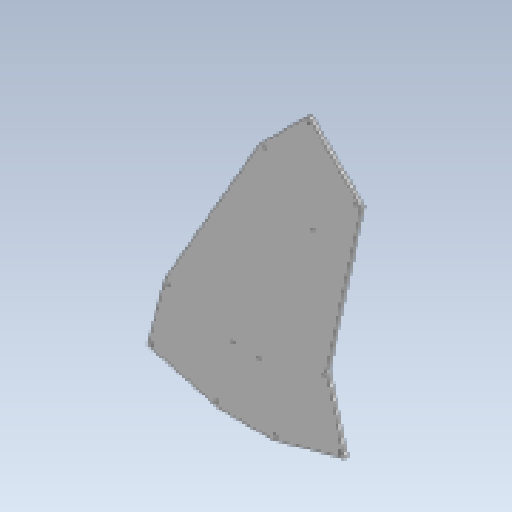
# Autodesk Inventor part: wdfs_mcnm1_base
Saved by Autodesk Inventor 2027.1 (Build 311270010, 270A)
## iProperties
Created: 2026-10-20
Part Number: wdfs_mcnm1_base
Material: ラワン材、メランティ
Document SubType Name: Modeling
Designer: ug_nd
Density: 0.416 g/cm^3
Appearance: マホガニー材 - 硬質 塗装 濃い色 標準の光沢
Author: ug_nd
Autodesk Inventor part; units mm, degrees
ref_plane "YZ Plane" through (0, 0, 0) normal (1, 0, 0) x (0, 1, 0)
ref_plane "XZ Plane" through (0, 0, 0) normal (0, 1, 0) x (-1, 0, 0)
ref_plane "XY Plane" through (0, 0, 0) normal (0, 0, 1) x (1, 0, 0)
sketch "スケッチ1" plane through (0, 0, 0) normal (0, 0, 1) x (1, 0, 0)
  line L0 (0, -280) -> (0, 280) construction
  circle A0 centre (0, 0) radius 200 construction
  line L1 (0, 200) -> (111.3693, 88.6307) construction
  line L2 (-21.0718, -140.764) -> (-173.2051, -100) construction
  line L3 (-173.2051, -100) -> (0, 0) construction
  line L4 (-98.9371, -75.9008) -> (-120.9367, -158.0045)
  line L5 (-120.9367, -158.0045) -> (-32.0716, -181.8158)
  line L6 (98.9371, -75.9008) -> (120.9367, -158.0045)
  line L7 (120.9367, -158.0045) -> (32.0716, -181.8158)
  line L8 (-32.0716, -181.8158) -> (32.0716, -181.8158)
  line L9 (173.2051, -100) -> (0, 0) construction
  line L10 (16.2635, 123.6325) -> (76.3675, 183.7365)
  line L11 (76.3675, 183.7365) -> (141.4214, 118.6827)
  line L12 (16.2635, 123.6325) -> (-98.9371, -75.9008)
  line L13 (141.4214, 118.6827) -> (98.9371, -75.9008)
  circle A1 centre (-114.813, -154.469) radius 1.5
  circle A2 centre (-35.6071, -175.6921) radius 1.5
  circle A3 centre (-16.1957, -103.2477) radius 1.5
  circle A4 centre (-95.4016, -82.0245) radius 1.5
  line L14 (-98.9371, -75.9008) -> (-10.072, -99.7122) construction
  line L15 (-10.072, -99.7122) -> (-32.0716, -181.8158) construction
  circle A5 centre (114.813, -154.469) radius 1.5
  circle A6 centre (35.6071, -175.6921) radius 1.5
  circle A7 centre (16.1957, -103.2477) radius 1.5
  circle A8 centre (95.4016, -82.0245) radius 1.5
  circle A9 centre (76.3675, 176.6655) radius 1.5
  circle A10 centre (134.3503, 118.6827) radius 1.5
  circle A11 centre (81.3173, 65.6497) radius 1.5
  circle A12 centre (23.3345, 123.6325) radius 1.5
  dimension "d1" = 400
  dimension "d6" = 120
  dimension "d10" = 45
  dimension "d12" = 45
  dimension "d13" = 157.5
  dimension "d14" = 65.5
  dimension "d15" = 85
  dimension "d16" = 92
  dimension "d17" = 5
  dimension "d18" = 5
  dimension "d19" = 3
  dimension "d20" = 5
  dimension "d21" = 5
  dimension "d22" = 5
  dimension "d23" = 5
  dimension "d24" = 5
  dimension "d25" = 5
  constraints: 30 end point, 16 symmetric about line, 13 centre point, 4 perpendicular, 3 equal radius, 2 point on circle, 1 coincident, 1 equal length, 1 horizontal, 1 point on line, 8 other
  measures "d1" diameter of A0
  measures "d6" angle of L3 L0
  measures "d10" angle of L2 L3
  measures "d12" angle of L0 L1
  measures "d13" distance of L2.start L2.end
  measures "d14" distance from line of L4 L2.end
  measures "d15" distance of L4.start L4.end
  measures "d16" distance of L4.end L5.end
  measures "d17" distance from line of A1.centre L4
  measures "d18" distance from line of L5 A1.centre
  measures "d19" diameter of A1
  measures "d20" distance from line of L5 A2.centre
  measures "d21" distance from line of L15 A2.centre
  measures "d22" distance from line of L15 A3.centre
  measures "d23" distance from line of L14 A3.centre
  measures "d24" distance from line of L14 A4.centre
  measures "d25" distance from line of L4 A4.centre
extrude "押し出し1" add sketch "スケッチ1" along normal mid plane 4
